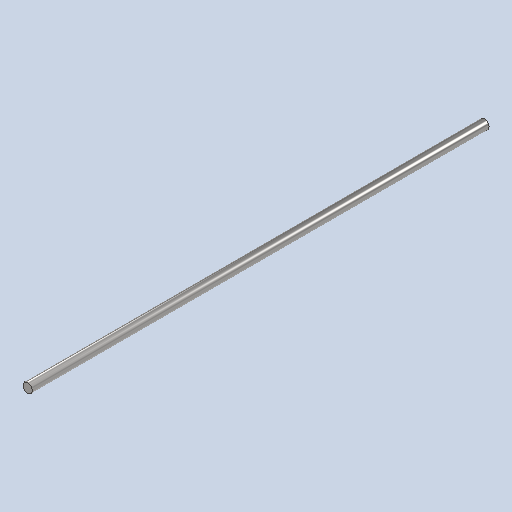
# Autodesk Inventor part: RDS-1502 Mixer Shaft 2
Saved by Autodesk Inventor 2026.2 (Build 302298000, 298)
## iProperties
Created: 2026-10-18
Part Number: RDS-1502 Mixer Shaft 2
Material: Stainless Steel, Austenitic
Description: Mixer shaft 2, rough
Document SubType Name: Modeling
Designer: admin
Stock Number: Вал 2 мешалки (ставится изнутри, дюймовая резьба к валу 1)
Density: 8 g/cm^3
Appearance: Semi-Polished
Author: admin
Autodesk Inventor part; units mm, degrees
ref_plane "YZ Plane" through (0, 0, 0) normal (1, 0, 0) x (0, 1, 0)
ref_plane "XZ Plane" through (0, 0, 0) normal (0, 1, 0) x (-1, 0, 0)
ref_plane "XY Plane" through (0, 0, 0) normal (0, 0, 1) x (1, 0, 0)
sketch "Sketch1" plane through (0, 0, 0) normal (0, 0, 1) x (1, 0, 0)
  circle A0 centre (0, 0) radius 16
  constraints: 1 centre point
extrude "Extrusion1" add sketch "Sketch1" along normal blind 1550
equation "\"d0\" = Shaft1502_Length"
equation "\"Shaft1502_Diam\" = 32"
equation "\"Shaft1502_Length\" = 1550"
body "Solid1"
